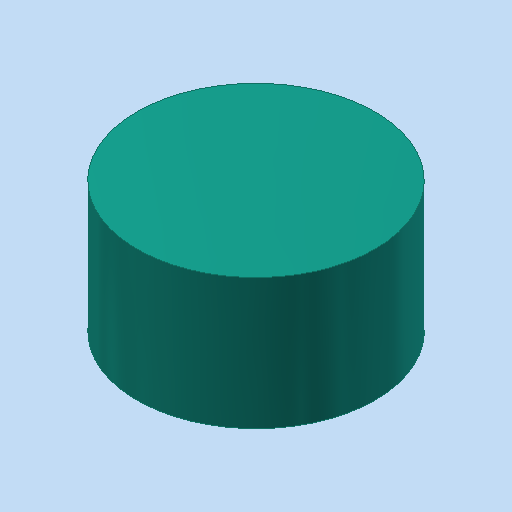
# Autodesk Inventor part: IQC21-8__20200702
Saved by Autodesk Inventor 2023.3 (Build 273359000, 359)
## iProperties
Created: 2007-08-24
Part Number: IQC21-8__20200702
Document SubType Name: Modeling
Designer: EKOMA
Description: =<RBPARTNOTITLE2>
Vendor: Pepperl + Fuchs
Density: 8.8 g/cm^3
Material: Generisch
Appearance: Türkis
Mass: 1.94628 g
Surface Area: 2.11115 cm^2
Volume: 0.221168 cm^3
RBPARTNOTITLE1: RFID-chip
RBPARTMADEOF: IQC21-8
RBPARTNOTITLE2: RFID-Datenpille
RBMATNO: =<Part Number>
RBMATERIAL: --
RBGBDIM_01: 0,000 mm
RBGBDIM_04: 0,000 mm
RBGBDIM_03: 0,000 mm
RBGBDIM_02: 0,000 mm
Händler: P&F
AnP_Kategorie: 2
AnP_Material: =<Material>
RBDRAWINGMISSINGSPEC: --
RBGBREMARKSINDEX: E
Author: EKOMA
Keywords: =<RBPARTMADEOF>
Comments: =<RBSURFACE2>
Revision Number: 01
Autodesk Inventor part; units mm, degrees
ref_plane "YZ Plane" through (0, 0, 0) normal (1, 0, 0) x (0, 1, 0)
ref_plane "XZ Plane" through (0, 0, 0) normal (0, 1, 0) x (-1, 0, 0)
ref_plane "XY Plane" through (0, 0, 0) normal (0, 0, 1) x (1, 0, 0)
sketch "Skizze1" plane through (0, 0, 0) normal (0, 0, 1) x (1, 0, 0)
  circle A0 centre (0, 0) radius 4
  dimension "d0" = 8
  constraints: 1 centre point, 1 coincident
  measures "d0" diameter of A0
extrude "Extrusion1" add sketch "Skizze1" along normal blind 4.4
equation "\"RBGBDIM_01\" = 0"
equation "\"RBGBDIM_02\" = 0"
equation "\"RBGBDIM_03\" = 0"
equation "\"RBGBDIM_04\" = 0"
